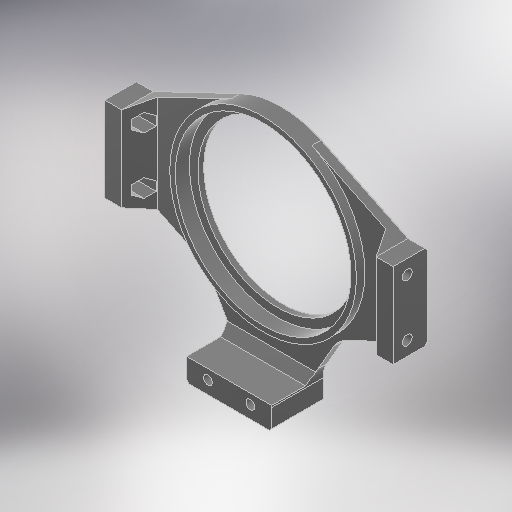
# Autodesk Inventor part: 3D_bearing-holder
Saved by Autodesk Inventor 2025.3 (Build 293356030, 356C)
## iProperties
Created: 2026-05-23
Part Number: 3D_bearing-holder
Material: 一般
Document SubType Name: Modeling
Designer: ibuki_ono
Density: 1 g/cm^3
Appearance: 滑らか - 黒
Author: ibuki_ono
## iProperties of the stored document 3D_bearing-holder_3D プリント.ipt
Created: 2026-05-23
Part Number: 3D_bearing-holder_3D プリント
Material: 一般
Document SubType Name: Modeling
Designer: ibuki_ono
Density: 1 g/cm^3
Appearance: 既定
Author: ibuki_ono
Autodesk Inventor part; units mm, degrees
ref_plane "YZ Plane" through (0, 0, 0) normal (1, 0, 0) x (0, 1, 0)
ref_plane "XZ Plane" through (0, 0, 0) normal (0, 1, 0) x (-1, 0, 0)
sketch "スケッチ1" plane through (0, 0, 0) normal (0, 0, 1) x (1, 0, 0)
  circle A0 centre (0, 0) radius 33
  circle A1 centre (0, 0) radius 28
  dimension "d0" = 66
  dimension "d1" = 56
  constraints: 2 centre point, 2 coincident
  measures "d0" diameter of A0
  measures "d1" diameter of A1
extrude "押し出し1" add sketch "スケッチ1" along normal blind 7
sketch "スケッチ2" plane through (0, 0, 7) normal (0, 0, 1) x (1, 0, 0)
  circle A0 centre (0, 0) radius 28 projected
  circle A1 centre (0, 0) radius 31.05
  dimension "d4" = 62.1
  constraints: 1 centre point, 1 coincident
  measures "d4" diameter of A1
extrude "押し出し2" cut sketch "スケッチ2" against normal blind 5
sketch "スケッチ3" plane through (0, 0, 0) normal (0, 0, -1) x (-1, 0, 0)
  line L0 (-51, 15) -> (51, 15)
  line L1 (51, 15) -> (51, -15)
  line L2 (51, -15) -> (-51, -15)
  line L3 (-51, -15) -> (-51, 15)
  line L4 (-51, 15) -> (51, -15) construction
  line L5 (51, 15) -> (-51, -15) construction
  circle A0 centre (0, 0) radius 33 projected
  line L6 (45, -15) -> (14.2838, -29.7485)
  line L7 (-14.2838, -29.7485) -> (-45, -15)
  line L8 (-14.2838, 29.7485) -> (-45, 15)
  line L9 (45, 15) -> (14.2838, 29.7485)
  circle A1 centre (0, 0) radius 33 projected
  line L10 (15, -29.3939) -> (-15, -29.3939)
  line L11 (-15, -29.3939) -> (-15, -50)
  line L12 (-15, -50) -> (15, -50)
  line L13 (15, -50) -> (15, -29.3939)
  line L14 (28.573, -16.5101) -> (15, -40)
  line L15 (-15, -40) -> (-28.573, -16.5101)
  point P0 (15, -29.3939)
  point P1 (-15, -29.3939)
  point P2 (-23.4731, -25.3362)
  point P3 (23.4731, -25.3362)
  point P4 (-15, -29.4046)
  point P5 (15, -29.4046)
  point P6 (-28.573, -16.5101)
  dimension "d7" = 102
  dimension "d8" = 30
  dimension "d9" = 6
  dimension "d10" = 6
  dimension "d11" = 6
  dimension "d12" = 6
  dimension "d71" = 30
  dimension "d72" = 40
  dimension "d73" = 40
  dimension "d74" = 50
  constraints: 32 end point, 6 point on line, 4 parallel, 4 point on circle, 4 tangent, 2 horizontal, 2 midpoint, 2 perpendicular, 7 other
  measures "d7" distance of L1.end L2.end
  measures "d8" distance of L0.end L1.end
  measures "d9" distance from line of L1 L6.start
  measures "d10" distance from line of L1 L9.start
  measures "d11" distance from line of L7.end L3
  measures "d12" distance from line of L8.end L3
  measures "d71" distance of L12.end L11.end
  measures "d72" vertical distance of point (0, 0) L14.end
  measures "d73" vertical distance of point (0, 0) L15.start
  measures "d74" distance from line of point (0, 0) L12
extrude "押し出し3" add sketch "スケッチ3" against normal blind 4 contours L0 A0 L2 L3 | L8 A0 L0 | L2 A0 L15 L7 | A0 L9 L0 | L0 L1 L2 A0 | L15 A0 L11 L7 | L7 L11 L15 | L2 L6 L14 A0 | L11 A0 L7 | L7 A0 L6 L13 L12 L11 | L14 L6 L13 A0 | L14 L13 L6 | L13 L6 A0
sketch "スケッチ9" plane through (51, -15, 0) normal (1, 0, 0) x (0, 0, -1)
  line L0 (0, 30) -> (0, 0) projected
  line L1 (0, 30) -> (-4, 30) projected
  line L2 (-4, 0) -> (-4, 30) projected
  line L3 (0, 0) -> (-4, 0) projected
  line L4 (0, 0) -> (-12, 0)
  line L5 (-12, 0) -> (-12, 30)
  line L6 (-12, 30) -> (0, 30)
  line L7 (0, 30) -> (0, 0)
  point P0 (0, 15)
  point P1 (-4, 0)
  dimension "d44" = 12
  constraints: 8 end point, 2 parallel, 1 horizontal, 1 perpendicular
  measures "d44" distance of L0.start L5.end
extrude "押し出し8" add sketch "スケッチ9" against normal blind 6 contours L2 L4 L5 L6
chamfer "面取り4" distance 8 angle 30 1 edges at (45, 0, 4) measured on face at (45, 0, 4.5)
sketch "スケッチ10" plane through (51, -15, 0) normal (1, 0, 0) x (0, 0, -1)
  line L0 (-7, 30) -> (-7, 0) construction
  line L1 (-12, 30) -> (-12, 0) projected
  line L2 (0, 30) -> (-12, 30) projected
  line L3 (0, 0) -> (-12, 0) projected
  point P0 (0, 15)
  point P1 (-7, 5)
  point P2 (-7, 25)
  dimension "d64" = 5
  dimension "d65" = 5
  dimension "d66" = 5
  constraints: 4 point on line, 2 end point
  measures "d64" distance between parallel lines of L0 L1
  measures "d65" distance from line of L2 point (-7, 25)
  measures "d66" distance from line of L3 point (-7, 5)
hole "穴2" at (51, -10, 7) at (51, 10, 7) direction (-1, 0, 0) diameter 3.5 end up to surface
ref_plane "作業平面1" through (40.3812, 0, 4) normal (1, 0, 0) x (0, -1, 0)
sketch "スケッチ11" plane through (40.3812, 0, 4) normal (1, 0, 0) x (0, -1, 0)
  circle A0 centre (10, -3) radius 1.75 projected
  circle A1 centre (-10, -3) radius 1.75 projected
  line L0 (-13.1754, -3) -> (-11.5877, -0.25)
  line L1 (-11.5877, -0.25) -> (-8.4123, -0.25)
  line L2 (-8.4123, -0.25) -> (-6.8246, -3)
  line L3 (-6.8246, -3) -> (-8.4123, -5.75)
  line L4 (-8.4123, -5.75) -> (-11.5877, -5.75)
  line L5 (-11.5877, -5.75) -> (-13.1754, -3)
  line L6 (6.8246, -3) -> (8.4123, -0.25)
  line L7 (8.4123, -0.25) -> (11.5877, -0.25)
  line L8 (11.5877, -0.25) -> (13.1754, -3)
  line L9 (13.1754, -3) -> (11.5877, -5.75)
  line L10 (11.5877, -5.75) -> (8.4123, -5.75)
  line L11 (8.4123, -5.75) -> (6.8246, -3)
  point P0 (0, 4)
  point P1 (-10, -3)
  point P2 (10, -3)
  dimension "d60" = 5.5
  dimension "d61" = 5.5
  constraints: 24 end point, 2 coincident, 2 horizontal alignment, 26 other
  measures "d60" distance between parallel lines of L1 L4
  measures "d61" distance between parallel lines of L7 L10
extrude "押し出し9" cut sketch "スケッチ11" along normal blind 8
mirror "ミラー3" about plane through (0, 0, 0) normal (1, 0, 0) of "押し出し8", "面取り4", "穴2", "押し出し9"
sketch "スケッチ12" plane through (0, 0, 4) normal (0, 0, 1) x (1, 0, 0)
  line L0 (-15, -50) -> (15, -50) projected
  line L1 (-15, -40) -> (-15, -50) projected
  line L2 (15, -50) -> (15, -40) projected
  line L3 (-15, -50) -> (-15, -40) projected
  line L4 (15, -50) -> (-15, -50)
  line L5 (-15, -50) -> (-15, -42)
  line L6 (-15, -42) -> (15, -42)
  line L7 (15, -42) -> (15, -50)
  point P0 (0, 0)
  point P1 (15, -42)
  point P2 (-15, -42)
  dimension "d75" = 8
  constraints: 8 end point, 2 parallel, 1 horizontal, 1 perpendicular, 1 point on line
  measures "d75" distance of L4.end L5.end
extrude "押し出し10" add sketch "スケッチ12" along normal blind 15
sketch "スケッチ13" plane through (0, 0, 0) normal (0, 0, -1) x (-1, 0, 0)
  line L0 (15, -50) -> (15, -40) projected
  line L1 (-15, -40) -> (-15, -50) projected
  line L2 (15, -45.5) -> (-15, -45.5) construction
  line L3 (-15, -50) -> (15, -50) construction
  point P0 (0, 0)
  point P1 (7.5, -45.5)
  point P2 (-7.5, -45.5)
  dimension "d78" = 4.5
  dimension "d79" = 7.5
  dimension "d80" = 7.5
  constraints: 4 point on line, 2 end point, 1 perpendicular
  measures "d78" distance between parallel lines of L3 L2
  measures "d79" distance from line of L0 point (7.5, -45.5)
  measures "d80" distance from line of L1 point (-7.5, -45.5)
hole "穴3" at (-7.5, -45.5, 0) at (7.5, -45.5, 0) direction (0, 0, 1) diameter 3.2 end through all counterbore diameter 6 counterbore depth 14
sketch "スケッチ14" plane through (-7.5, -45.5, 14) normal (0, 0, -1) x (-1, 0, 0)
  circle A0 centre (0, 0) radius 3 projected
  circle A1 centre (0, 0) radius 1.6 projected
  line L0 (2.5377, -1.6) -> (-2.5377, -1.6)
  line L1 (-2.6545, -1.3977) -> (-0.1168, 2.9977)
  line L2 (-2.6545, -1.3977) -> (2.4209, -1.3977) construction
  circle A2 centre (0, 0) radius 3 projected
  line L3 (0.1168, 2.9977) -> (2.6545, -1.3977)
  line L4 (0.1168, 2.9977) -> (5.1922, 2.9977) construction
  point P0 (-7.5, 45.5)
  point P1 (1.3856, 0.8)
  point P2 (0.1168, 2.9977)
  point P3 (-0.1168, 2.9977)
  point P4 (-1.3856, 0.8)
  point P5 (2.6545, -1.3977)
  point P6 (0, -1.6)
  dimension "d88" = 60
  dimension "d89" = 60
  constraints: 10 end point, 6 point on circle, 3 horizontal, 3 tangent, 2 equal length
  measures "d88" angle of L2 L1
  measures "d89" angle of L3 L4
extrude "押し出し11" cut sketch "スケッチ14" against normal blind 0.2 contours L3 A1 L1 A0 | A0 L0 A1 L3 | L1 A1 L0 A0
mirror "ミラー4" about plane through (0, 0, 0) normal (1, 0, 0) of "押し出し11"
chamfer "面取り5" distance 0.8 angle 45 2 edges at (-15, -50, 9.5) (15, -50, 9.5)
chamfer "面取り6" distance 3 angle 45 1 edges at (0, -42, 4)
fillet "フィレット1" radius 10 4 edges at (-23.4731, -25.3362, 2) (-15, -40, 2.5) (15, -40, 2.5) (23.4731, -25.3362, 2)
chamfer "面取り7" distance 0.8 angle 45 20 edges at (-29.6419, 22.3742, 0) (0, 33, 0) (29.6419, 22.3742, 0) (48, 15, 0) (48, -15, 0) (35.6288, -19.4996, 0) (23.7899, -25.6782, 0) (19.1346, -32.8446, 0) (15.3412, -40.0915, 0) (15, -45.9407, 0) (0, -50, 0) (14.6, -49.6, 0) (-14.6, -49.6, 0) (-15, -45.9407, 0) (-15.3412, -40.0915, 0) (-19.1346, -32.8446, 0) (-23.7899, -25.6782, 0) (-35.6288, -19.4996, 0) (-48, -15, 0) (-48, 15, 0)
equation "\"d10\" = d9"
equation "\"d11\" = d9"
equation "\"d12\" = d9"
equation "\"d73\" = d72"
equation "\"d66\" = d65"
equation "\"d61\" = d60"
equation "\"d80\" = d79"
